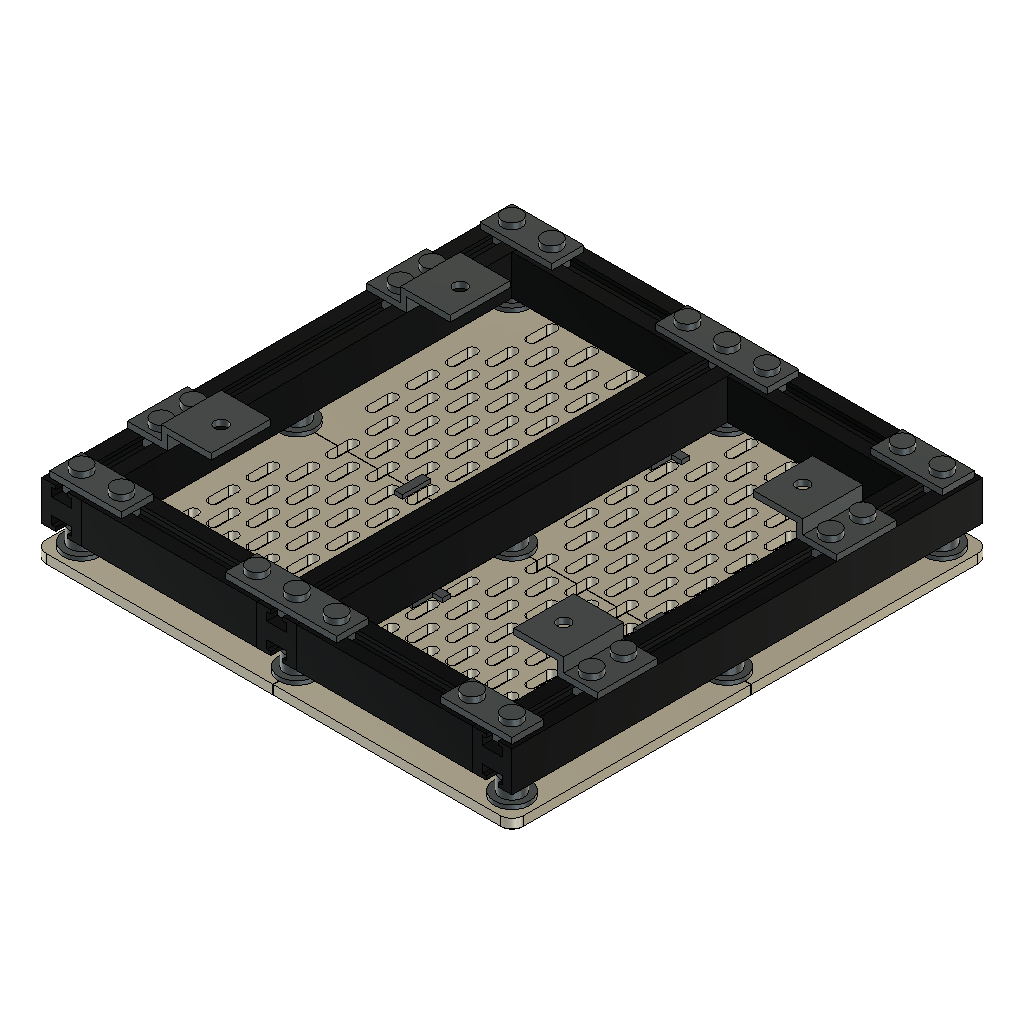
frame-assembly-v02 (Autodesk Fusion 360 design; units mm, degrees)
part number: 2026-10-27-14-19-07-166
part number: 2026-10-27-14-19-07-529
part number: 2026-10-27-14-19-09-809
part number: 2026-10-27-14-19-13-268
part number: 2026-10-27-14-19-18-051
part number: 2026-10-27-14-19-24-139
part number: 2026-10-27-14-19-25-781
part number: 2026-10-27-14-19-27-655
part number: 2026-10-27-14-19-31-529
part number: 2026-10-27-14-19-36-193
part number: 2026-10-27-14-19-39-612
part number: 2026-10-27-14-19-43-334
part number: 2026-10-27-14-19-47-364
part number: 2026-10-27-14-19-51-904
part number: 2026-10-27-14-19-56-573
part number: 2026-10-27-14-20-01-501
part number: 2026-10-27-14-20-06-731
part number: 2026-10-27-14-20-09-539
part number: 2026-10-27-14-20-12-443
part number: 2026-10-27-14-20-16-554
part number: 2026-10-27-14-20-19-669
part number: 2026-10-27-14-20-23-649
part number: 2026-10-27-14-20-26-963
part number: 2026-10-27-14-20-30-408
part number: 2026-10-27-14-20-35-629
part number: 2026-10-27-14-20-39-250
part number: 2026-10-27-14-20-43-608
part number: 2026-10-27-14-20-47-417
part number: 2026-10-27-14-20-51-282
part number: 2026-10-27-14-20-56-790
part number: 2026-10-27-14-21-00-901
part number: 2026-10-27-14-21-05-969
part number: 2026-10-27-14-21-10-301
part number: 2026-10-27-14-21-14-740
part number: 2026-10-27-14-21-20-864
part number: 2026-10-27-14-21-25-515
part number: 2026-10-27-14-21-31-135
part number: 2026-10-27-14-21-36-008
part number: 2026-10-27-14-21-40-945
part number: 2026-10-27-14-21-47-902
part number: 2026-10-27-14-21-53-029
part number: 2026-10-27-14-21-59-262
part number: 2026-10-27-14-22-04-647
part number: 2026-10-27-14-22-10-209
part number: 2026-10-27-14-22-17-939
part number: 2026-10-27-14-22-23-788
part number: 2026-10-27-14-22-30-837
part number: 2026-10-27-14-22-36-914
part number: 2026-10-27-14-22-43-023
part number: 2026-10-27-14-22-51-516
part number: 2026-10-27-14-22-58-163
part number: 2026-10-27-14-23-05-832
part number: 2026-10-27-14-23-12-387
part number: 2026-10-27-14-23-18-901
part number: 2026-10-27-14-23-27-984
part number: 2026-10-27-14-23-34-860
part number: 2026-10-27-14-23-42-988
part number: 2026-10-27-14-23-50-025
part number: 2026-10-27-14-23-57-272
part number: 2026-10-27-14-24-07-126
part number: 2026-10-27-14-24-14-511
part number: 2026-10-27-14-25-58-757
part number: 2026-10-27-14-26-07-708
part number: 2026-10-27-14-26-15-601
part number: 2026-10-27-14-26-28-880
part number: 2026-10-27-14-26-37-122
part number: 2026-10-27-14-26-46-848
part number: 2026-10-27-14-26-56-585
part number: 2026-10-27-14-27-05-195
part number: 2026-10-27-14-27-19-539
part number: 2026-10-27-14-27-28-473
part number: 2026-10-27-14-27-43-465
part number: 2026-10-27-14-27-53-465
part number: 2026-10-27-14-28-04-862
part number: 2026-10-27-14-28-15-884
part number: 2026-10-27-14-28-25-517
part number: 2026-10-27-14-28-41-860
part number: 2026-10-27-14-28-51-770
part number: 2026-10-27-14-29-29-498
part number: 2026-10-27-14-29-41-777
part number: 2026-10-27-14-29-52-480
part number: 2026-10-27-14-30-10-482
part number: 2026-10-27-14-30-21-478
part number: 2026-10-27-14-30-34-709
part number: 2026-10-27-14-30-47-817
part number: 2026-10-27-14-30-59-317
part number: 2026-10-27-14-31-18-533
part number: 2026-10-27-14-31-30-323
part number: 2026-10-27-14-31-49-934
part number: 2026-10-27-14-32-02-066
part number: 2026-10-27-14-32-16-521
part number: 2026-10-27-14-32-30-791
part number: 2026-10-27-14-32-43-473
part number: 2026-10-27-14-33-04-473
part number: 2026-10-27-14-33-17-387
part number: 2026-10-27-14-34-51-038
part number: 2026-10-27-14-35-27-564
part number: 2026-10-27-14-35-40-483
part number: 2026-10-27-14-36-02-021
part number: 2026-10-27-14-36-15-429
part number: 2026-10-27-14-36-31-161
part number: 2026-10-27-14-37-10-809
part number: 2026-10-27-14-37-25-035
part number: 2026-10-27-14-37-48-193
part number: 2026-10-27-14-38-03-120
part number: 2026-10-27-14-38-20-090
part number: 2026-10-27-14-39-02-547
part number: 2026-10-27-14-39-17-368
part number: 2026-10-27-14-39-42-212
part number: 2026-10-27-14-39-58-334
part number: 2026-10-27-14-40-16-332
part number: 2026-10-27-14-41-01-723
part number: 2026-10-27-14-41-17-623
part number: 2026-10-27-14-41-44-437
part number: 2026-10-27-14-42-00-770
Autodesk Fusion 360 part; units mm, degrees
(part 1 of 7)
sketch "01 Panel blank sketch" plane through (0, 0, 0) normal (0, 0, 1) x (1, 0, 0) in component "Panel lower left"
  line L0 (0.1, 0.1) -> (119.9, 0.1)
  line L1 (119.9, 0.1) -> (119.9, 119.9)
  line L2 (119.9, 119.9) -> (0.1, 119.9)
  line L3 (0.1, 119.9) -> (0.1, 0.1)
  dimension "d31" = 0.1
  dimension "d32" = 0.1
  dimension "d33" = 119.8
  dimension "d34" = 119.8
  constraint horizontal L0
  constraint vertical L1
  constraint horizontal L2
  constraint vertical L3
  measures "d31" horizontal distance of origin L0.start
  measures "d32" vertical distance of origin L0.start
  measures "d33" horizontal distance of L0.start L0.end
  measures "d34" vertical distance of L0.end L1.end
extrude "01 Panel blank" add sketch "01 Panel blank sketch" along normal blind 5 makes body 1 in component "Panel lower left"
fillet "02 Rounded exterior corner" radius 6 1 edges at (0.1, 0.1, 2.5) on bodies 1 in component "Panel lower left"
sketch "03 A main constrained seed" plane through (0, 0, 0) normal (0, 0, 1) x (1, 0, 0) in component "Panel lower left"
  line L0 (47.5, 25) -> (47.5, 35)
  arc A0 (47.5, 35) -> (42.5, 35) centre (45, 35) ccw
  line L1 (42.5, 35) -> (42.5, 25)
  arc A1 (42.5, 25) -> (47.5, 25) centre (45, 25) ccw
  line L2 (45, 25) -> (45, 35) construction
  line L3 (45, 25) -> (55, 25) construction
  dimension "d39" = 5
  dimension "d40" = 10
  dimension "d41" = 90
  dimension "d42" = 10
  dimension "d43" = 45
  dimension "d44" = 25
  constraint tangent L0 A0
  constraint tangent A0 L1
  constraint tangent L1 A1
  constraint tangent L0 A1
  constraint parallel L0 L1
  constraint horizontal L3
  measures "d39" diameter of A0
  measures "d40" distance of A1.centre A0.centre
  measures "d41" angle of L2 L3
  measures "d42" horizontal distance of A1.centre L3.end
  measures "d43" horizontal distance of origin A1.centre
  measures "d44" vertical distance of origin A1.centre
extrude "03 A main through cut" cut sketch "03 A main constrained seed" along normal blind 5 bodies 1 in component "Panel lower left"
pattern_linear "03 A main lattice" count 4 spacing 20 along (1, 0, 0) count 5 spacing 20 along (0, 1, 0) of "03 A main through cut" in component "Panel lower left"
sketch "04 A end strip constrained seed" plane through (0, 0, 0) normal (0, 0, 1) x (1, 0, 0) in component "Panel lower left"
  line L0 (27.5, 45) -> (27.5, 55)
  arc A0 (27.5, 55) -> (22.5, 55) centre (25, 55) ccw
  line L1 (22.5, 55) -> (22.5, 45)
  arc A1 (22.5, 45) -> (27.5, 45) centre (25, 45) ccw
  line L2 (25, 45) -> (25, 55) construction
  line L3 (25, 45) -> (35, 45) construction
  dimension "d51" = 5
  dimension "d52" = 10
  dimension "d53" = 90
  dimension "d54" = 10
  dimension "d55" = 25
  dimension "d56" = 45
  constraint tangent L0 A0
  constraint tangent A0 L1
  constraint tangent L1 A1
  constraint tangent L0 A1
  constraint parallel L0 L1
  constraint horizontal L3
  measures "d51" diameter of A0
  measures "d52" distance of A1.centre A0.centre
  measures "d53" angle of L2 L3
  measures "d54" horizontal distance of A1.centre L3.end
  measures "d55" horizontal distance of origin A1.centre
  measures "d56" vertical distance of origin A1.centre
extrude "04 A end strip through cut" cut sketch "04 A end strip constrained seed" along normal blind 5 bodies 1 in component "Panel lower left"
pattern_linear "04 A end strip lattice" count 1 spacing 20 along (1, 0, 0) count 3 spacing 20 along (0, 1, 0) of "04 A end strip through cut" in component "Panel lower left"
sketch "05 B main constrained seed" plane through (0, 0, 0) normal (0, 0, 1) x (1, 0, 0) in component "Panel lower left"
  line L0 (37.5, 15) -> (37.5, 25)
  arc A0 (37.5, 25) -> (32.5, 25) centre (35, 25) ccw
  line L1 (32.5, 25) -> (32.5, 15)
  arc A1 (32.5, 15) -> (37.5, 15) centre (35, 15) ccw
  line L2 (35, 15) -> (35, 25) construction
  line L3 (35, 15) -> (45, 15) construction
  dimension "d63" = 5
  dimension "d64" = 10
  dimension "d65" = 90
  dimension "d66" = 10
  dimension "d67" = 35
  dimension "d68" = 15
  constraint tangent L0 A0
  constraint tangent A0 L1
  constraint tangent L1 A1
  constraint tangent L0 A1
  constraint parallel L0 L1
  constraint horizontal L3
  measures "d63" diameter of A0
  measures "d64" distance of A1.centre A0.centre
  measures "d65" angle of L2 L3
  measures "d66" horizontal distance of A1.centre L3.end
  measures "d67" horizontal distance of origin A1.centre
  measures "d68" vertical distance of origin A1.centre
extrude "05 B main through cut" cut sketch "05 B main constrained seed" along normal blind 5 bodies 1 in component "Panel lower left"
pattern_linear "05 B main lattice" count 4 spacing 20 along (1, 0, 0) count 6 spacing 20 along (0, 1, 0) of "05 B main through cut" in component "Panel lower left"
sketch "06 B end strip constrained seed" plane through (0, 0, 0) normal (0, 0, 1) x (1, 0, 0) in component "Panel lower left"
  line L0 (117.5, 35) -> (117.5, 45)
  arc A0 (117.5, 45) -> (112.5, 45) centre (115, 45) ccw
  line L1 (112.5, 45) -> (112.5, 35)
  arc A1 (112.5, 35) -> (117.5, 35) centre (115, 35) ccw
  line L2 (115, 35) -> (115, 45) construction
  line L3 (115, 35) -> (125, 35) construction
  dimension "d75" = 5
  dimension "d76" = 10
  dimension "d77" = 90
  dimension "d78" = 10
  dimension "d79" = 115
  dimension "d80" = 35
  constraint tangent L0 A0
  constraint tangent A0 L1
  constraint tangent L1 A1
  constraint tangent L0 A1
  constraint parallel L0 L1
  constraint horizontal L3
  measures "d75" diameter of A0
  measures "d76" distance of A1.centre A0.centre
  measures "d77" angle of L2 L3
  measures "d78" horizontal distance of A1.centre L3.end
  measures "d79" horizontal distance of origin A1.centre
  measures "d80" vertical distance of origin A1.centre
extrude "06 B end strip through cut" cut sketch "06 B end strip constrained seed" along normal blind 5 bodies 1 in component "Panel lower left"
pattern_linear "06 B end strip lattice" count 1 spacing 20 along (1, 0, 0) count 4 spacing 20 along (0, 1, 0) of "06 B end strip through cut" in component "Panel lower left"
sketch "07 Shared node clearance sketch" plane through (0, 0, 0) normal (0, 0, 1) x (1, 0, 0) in component "Panel lower left"
  circle A0 centre (12, 12) radius 4.2
  dimension "d87" = 12
  dimension "d88" = 12
  dimension "d89" = 8.4
  measures "d87" horizontal distance of origin A0.centre
  measures "d88" vertical distance of origin A0.centre
  measures "d89" diameter of A0
extrude "07 Shared node clearance" cut sketch "07 Shared node clearance sketch" along normal blind 5 bodies 1 in component "Panel lower left"
sketch "07 Shared node clearance sketch (1)" plane through (0, 0, 0) normal (0, 0, 1) x (1, 0, 0) in component "Panel lower left"
  circle A0 centre (12, 120) radius 4.2
  dimension "d92" = 12
  dimension "d93" = 120
  dimension "d94" = 8.4
  measures "d92" horizontal distance of origin A0.centre
  measures "d93" vertical distance of origin A0.centre
  measures "d94" diameter of A0
extrude "07 Shared node clearance (1)" cut sketch "07 Shared node clearance sketch (1)" along normal blind 5 bodies 1 in component "Panel lower left"
sketch "07 Shared node clearance sketch (2)" plane through (0, 0, 0) normal (0, 0, 1) x (1, 0, 0) in component "Panel lower left"
  circle A0 centre (120, 12) radius 4.2
  dimension "d97" = 120
  dimension "d98" = 12
  dimension "d99" = 8.4
  measures "d97" horizontal distance of origin A0.centre
  measures "d98" vertical distance of origin A0.centre
  measures "d99" diameter of A0
extrude "07 Shared node clearance (2)" cut sketch "07 Shared node clearance sketch (2)" along normal blind 5 bodies 1 in component "Panel lower left"
sketch "07 Shared node clearance sketch (3)" plane through (0, 0, 0) normal (0, 0, 1) x (1, 0, 0) in component "Panel lower left"
  circle A0 centre (120, 120) radius 4.2
  dimension "d102" = 120
  dimension "d103" = 120
  dimension "d104" = 8.4
  measures "d102" horizontal distance of origin A0.centre
  measures "d103" vertical distance of origin A0.centre
  measures "d104" diameter of A0
extrude "07 Shared node clearance (3)" cut sketch "07 Shared node clearance sketch (3)" along normal blind 5 bodies 1 in component "Panel lower left"
fillet "08 Rounded slot entrances and face edges" radius 0.4 2 faces at (7.5667, 63.6667, 0) (7.5667, 63.6667, 0) on bodies 1 in component "Panel lower left"
ref_plane "WorkPlane1" through (0, 0, 5) normal (0, 0, 1) x (1, 0, 0) in component "Panel lower left"
sketch "09 Blind rear key socket sketch" plane through (0, 0, 5) normal (0, 0, 1) x (1, 0, 0) in component "Panel lower left"
  circle A0 centre (115, 70) radius 1.7
  dimension "d111" = 115
  dimension "d112" = 70
  dimension "d113" = 3.4
  measures "d111" horizontal distance of origin A0.centre
  measures "d112" vertical distance of origin A0.centre
  measures "d113" diameter of A0
extrude "09 Blind rear key socket" cut sketch "09 Blind rear key socket sketch" against normal blind 1 bodies 1 in component "Panel lower left"
ref_plane "WorkPlane2" through (0, 0, 5) normal (0, 0, 1) x (1, 0, 0) in component "Panel lower left"
sketch "09 Blind rear key socket sketch (1)" plane through (0, 0, 5) normal (0, 0, 1) x (1, 0, 0) in component "Panel lower left"
  circle A0 centre (70, 115) radius 1.7
  dimension "d118" = 70
  dimension "d119" = 115
  dimension "d120" = 3.4
  measures "d118" horizontal distance of origin A0.centre
  measures "d119" vertical distance of origin A0.centre
  measures "d120" diameter of A0
extrude "09 Blind rear key socket (1)" cut sketch "09 Blind rear key socket sketch (1)" against normal blind 1 bodies 1 in component "Panel lower left"
sketch "01 Panel blank sketch (2)" plane through (0, 0, 0) normal (0, 0, 1) x (1, 0, 0) in component "Panel lower right"
  line L0 (120.1, 0.1) -> (239.9, 0.1)
  line L1 (239.9, 0.1) -> (239.9, 119.9)
  line L2 (239.9, 119.9) -> (120.1, 119.9)
  line L3 (120.1, 119.9) -> (120.1, 0.1)
  dimension "d127" = 120.1
  dimension "d128" = 0.1
  dimension "d129" = 119.8
  dimension "d130" = 119.8
  constraint horizontal L0
  constraint vertical L1
  constraint horizontal L2
  constraint vertical L3
  measures "d127" horizontal distance of origin L0.start
  measures "d128" vertical distance of origin L0.start
  measures "d129" horizontal distance of L0.start L0.end
  measures "d130" vertical distance of L0.end L1.end
extrude "01 Panel blank'" add sketch "01 Panel blank sketch (2)" along normal blind 5 separate body makes body 2 in component "Panel lower right"
fillet "02 Rounded exterior corner'" radius 6 1 edges at (239.9, 0.1, 2.5) on bodies 2 in component "Panel lower right"
sketch "03 A main constrained seed (2)" plane through (0, 0, 0) normal (0, 0, 1) x (1, 0, 0) in component "Panel lower right"
  line L0 (147.5, 25) -> (147.5, 35)
  arc A0 (147.5, 35) -> (142.5, 35) centre (145, 35) ccw
  line L1 (142.5, 35) -> (142.5, 25)
  arc A1 (142.5, 25) -> (147.5, 25) centre (145, 25) ccw
  line L2 (145, 25) -> (145, 35) construction
  line L3 (145, 25) -> (155, 25) construction
  dimension "d135" = 5
  dimension "d136" = 10
  dimension "d137" = 90
  dimension "d138" = 10
  dimension "d139" = 145
  dimension "d140" = 25
  constraint tangent L0 A0
  constraint tangent A0 L1
  constraint tangent L1 A1
  constraint tangent L0 A1
  constraint parallel L0 L1
  constraint horizontal L3
  measures "d135" diameter of A0
  measures "d136" distance of A1.centre A0.centre
  measures "d137" angle of L2 L3
  measures "d138" horizontal distance of A1.centre L3.end
  measures "d139" horizontal distance of origin A1.centre
  measures "d140" vertical distance of origin A1.centre
extrude "03 A main through cut'" cut sketch "03 A main constrained seed (2)" along normal blind 5 bodies 2 in component "Panel lower right"
pattern_linear "03 A main lattice'" count 4 spacing 20 along (1, 0, 0) count 5 spacing 20 along (0, 1, 0) of "03 A main through cut'" in component "Panel lower right"
sketch "04 A end strip constrained seed (2)" plane through (0, 0, 0) normal (0, 0, 1) x (1, 0, 0) in component "Panel lower right"
  line L0 (127.5, 45) -> (127.5, 55)
  arc A0 (127.5, 55) -> (122.5, 55) centre (125, 55) ccw
  line L1 (122.5, 55) -> (122.5, 45)
  arc A1 (122.5, 45) -> (127.5, 45) centre (125, 45) ccw
  line L2 (125, 45) -> (125, 55) construction
  line L3 (125, 45) -> (135, 45) construction
  dimension "d147" = 5
  dimension "d148" = 10
  dimension "d149" = 90
  dimension "d150" = 10
  dimension "d151" = 125
  dimension "d152" = 45
  constraint tangent L0 A0
  constraint tangent A0 L1
  constraint tangent L1 A1
  constraint tangent L0 A1
  constraint parallel L0 L1
  constraint horizontal L3
  measures "d147" diameter of A0
  measures "d148" distance of A1.centre A0.centre
  measures "d149" angle of L2 L3
  measures "d150" horizontal distance of A1.centre L3.end
  measures "d151" horizontal distance of origin A1.centre
  measures "d152" vertical distance of origin A1.centre
extrude "04 A end strip through cut'" cut sketch "04 A end strip constrained seed (2)" along normal blind 5 bodies 2 in component "Panel lower right"
pattern_linear "04 A end strip lattice'" count 1 spacing 20 along (1, 0, 0) count 3 spacing 20 along (0, 1, 0) of "04 A end strip through cut'" in component "Panel lower right"
sketch "05 B main constrained seed (2)" plane through (0, 0, 0) normal (0, 0, 1) x (1, 0, 0) in component "Panel lower right"
  line L0 (137.5, 15) -> (137.5, 25)
  arc A0 (137.5, 25) -> (132.5, 25) centre (135, 25) ccw
  line L1 (132.5, 25) -> (132.5, 15)
  arc A1 (132.5, 15) -> (137.5, 15) centre (135, 15) ccw
  line L2 (135, 15) -> (135, 25) construction
  line L3 (135, 15) -> (145, 15) construction
  dimension "d159" = 5
  dimension "d160" = 10
  dimension "d161" = 90
  dimension "d162" = 10
  dimension "d163" = 135
  dimension "d164" = 15
  constraint tangent L0 A0
  constraint tangent A0 L1
  constraint tangent L1 A1
  constraint tangent L0 A1
  constraint parallel L0 L1
  constraint horizontal L3
  measures "d159" diameter of A0
  measures "d160" distance of A1.centre A0.centre
  measures "d161" angle of L2 L3
  measures "d162" horizontal distance of A1.centre L3.end
  measures "d163" horizontal distance of origin A1.centre
  measures "d164" vertical distance of origin A1.centre
extrude "05 B main through cut'" cut sketch "05 B main constrained seed (2)" along normal blind 5 bodies 2 in component "Panel lower right"
pattern_linear "05 B main lattice'" count 4 spacing 20 along (1, 0, 0) count 6 spacing 20 along (0, 1, 0) of "05 B main through cut'" in component "Panel lower right"
sketch "06 B end strip constrained seed (2)" plane through (0, 0, 0) normal (0, 0, 1) x (1, 0, 0) in component "Panel lower right"
  line L0 (217.5, 35) -> (217.5, 45)
  arc A0 (217.5, 45) -> (212.5, 45) centre (215, 45) ccw
  line L1 (212.5, 45) -> (212.5, 35)
  arc A1 (212.5, 35) -> (217.5, 35) centre (215, 35) ccw
  line L2 (215, 35) -> (215, 45) construction
  line L3 (215, 35) -> (225, 35) construction
  dimension "d171" = 5
  dimension "d172" = 10
  dimension "d173" = 90
  dimension "d174" = 10
  dimension "d175" = 215
  dimension "d176" = 35
  constraint tangent L0 A0
  constraint tangent A0 L1
  constraint tangent L1 A1
  constraint tangent L0 A1
  constraint parallel L0 L1
  constraint horizontal L3
  measures "d171" diameter of A0
  measures "d172" distance of A1.centre A0.centre
  measures "d173" angle of L2 L3
  measures "d174" horizontal distance of A1.centre L3.end
  measures "d175" horizontal distance of origin A1.centre
  measures "d176" vertical distance of origin A1.centre
extrude "06 B end strip through cut'" cut sketch "06 B end strip constrained seed (2)" along normal blind 5 bodies 2 in component "Panel lower right"
pattern_linear "06 B end strip lattice'" count 1 spacing 20 along (1, 0, 0) count 4 spacing 20 along (0, 1, 0) of "06 B end strip through cut'" in component "Panel lower right"
sketch "07 Shared node clearance sketch (4)" plane through (0, 0, 0) normal (0, 0, 1) x (1, 0, 0) in component "Panel lower right"
  circle A0 centre (120, 12) radius 4.2
  dimension "d183" = 120
  dimension "d184" = 12
  dimension "d185" = 8.4
  measures "d183" horizontal distance of origin A0.centre
  measures "d184" vertical distance of origin A0.centre
  measures "d185" diameter of A0
extrude "07 Shared node clearance'" cut sketch "07 Shared node clearance sketch (4)" along normal blind 5 bodies 2 in component "Panel lower right"
sketch "07 Shared node clearance sketch (1) (2)" plane through (0, 0, 0) normal (0, 0, 1) x (1, 0, 0) in component "Panel lower right"
  circle A0 centre (120, 120) radius 4.2
  dimension "d188" = 120
  dimension "d189" = 120
  dimension "d190" = 8.4
  measures "d188" horizontal distance of origin A0.centre
  measures "d189" vertical distance of origin A0.centre
  measures "d190" diameter of A0
extrude "07 Shared node clearance (1)'" cut sketch "07 Shared node clearance sketch (1) (2)" along normal blind 5 bodies 2 in component "Panel lower right"
sketch "07 Shared node clearance sketch (2) (2)" plane through (0, 0, 0) normal (0, 0, 1) x (1, 0, 0) in component "Panel lower right"
  circle A0 centre (228, 12) radius 4.2
  dimension "d193" = 228
  dimension "d194" = 12
  dimension "d195" = 8.4
  measures "d193" horizontal distance of origin A0.centre
  measures "d194" vertical distance of origin A0.centre
  measures "d195" diameter of A0
extrude "07 Shared node clearance (2)'" cut sketch "07 Shared node clearance sketch (2) (2)" along normal blind 5 bodies 2 in component "Panel lower right"
sketch "07 Shared node clearance sketch (3) (2)" plane through (0, 0, 0) normal (0, 0, 1) x (1, 0, 0) in component "Panel lower right"
  circle A0 centre (228, 120) radius 4.2
  dimension "d198" = 228
  dimension "d199" = 120
  dimension "d200" = 8.4
  measures "d198" horizontal distance of origin A0.centre
  measures "d199" vertical distance of origin A0.centre
  measures "d200" diameter of A0
extrude "07 Shared node clearance (3)'" cut sketch "07 Shared node clearance sketch (3) (2)" along normal blind 5 bodies 2 in component "Panel lower right"
fillet "08 Rounded slot entrances and face edges'" radius 0.4 2 faces at (232.4333, 63.6667, 0) (232.4333, 63.6667, 0) on bodies 2 in component "Panel lower right"
ref_plane "WorkPlane1" through (0, 0, 5) normal (0, 0, 1) x (1, 0, 0) in component "Panel lower right"
sketch "09 Blind rear key socket sketch (2)" plane through (0, 0, 5) normal (0, 0, 1) x (1, 0, 0) in component "Panel lower right"
  circle A0 centre (125, 80) radius 1.7
  dimension "d207" = 125
  dimension "d208" = 80
  dimension "d209" = 3.4
  measures "d207" horizontal distance of origin A0.centre
  measures "d208" vertical distance of origin A0.centre
  measures "d209" diameter of A0
extrude "09 Blind rear key socket'" cut sketch "09 Blind rear key socket sketch (2)" against normal blind 1 bodies 2 in component "Panel lower right"
ref_plane "WorkPlane2" through (0, 0, 5) normal (0, 0, 1) x (1, 0, 0) in component "Panel lower right"
sketch "09 Blind rear key socket sketch (1) (2)" plane through (0, 0, 5) normal (0, 0, 1) x (1, 0, 0) in component "Panel lower right"
  circle A0 centre (190, 115) radius 1.7
  dimension "d214" = 190
  dimension "d215" = 115
  dimension "d216" = 3.4
  measures "d214" horizontal distance of origin A0.centre
  measures "d215" vertical distance of origin A0.centre
  measures "d216" diameter of A0
extrude "09 Blind rear key socket (1)'" cut sketch "09 Blind rear key socket sketch (1) (2)" against normal blind 1 bodies 2 in component "Panel lower right"
sketch "01 Panel blank sketch (3)" plane through (0, 0, 0) normal (0, 0, 1) x (1, 0, 0) in component "Panel upper left"
  line L0 (0.1, 120.1) -> (119.9, 120.1)
  line L1 (119.9, 120.1) -> (119.9, 239.9)
  line L2 (119.9, 239.9) -> (0.1, 239.9)
  line L3 (0.1, 239.9) -> (0.1, 120.1)
  dimension "d223" = 0.1
  dimension "d224" = 120.1
  dimension "d225" = 119.8
  dimension "d226" = 119.8
  constraint horizontal L0
  constraint vertical L1
  constraint horizontal L2
  constraint vertical L3
  measures "d223" horizontal distance of origin L0.start
  measures "d224" vertical distance of origin L0.start
  measures "d225" horizontal distance of L0.start L0.end
  measures "d226" vertical distance of L0.end L1.end
extrude "01 Panel blank''" add sketch "01 Panel blank sketch (3)" along normal blind 5 separate body makes body 3 in component "Panel upper left"
fillet "02 Rounded exterior corner''" radius 6 1 edges at (0.1, 239.9, 2.5) on bodies 3 in component "Panel upper left"
sketch "03 A main constrained seed (3)" plane through (0, 0, 0) normal (0, 0, 1) x (1, 0, 0) in component "Panel upper left"
  line L0 (47.5, 125) -> (47.5, 135)
  arc A0 (47.5, 135) -> (42.5, 135) centre (45, 135) ccw
  line L1 (42.5, 135) -> (42.5, 125)
  arc A1 (42.5, 125) -> (47.5, 125) centre (45, 125) ccw
  line L2 (45, 125) -> (45, 135) construction
  line L3 (45, 125) -> (55, 125) construction
  dimension "d231" = 5
  dimension "d232" = 10
  dimension "d233" = 90
  dimension "d234" = 10
  dimension "d235" = 45
  dimension "d236" = 125
  constraint tangent L0 A0
  constraint tangent A0 L1
  constraint tangent L1 A1
  constraint tangent L0 A1
  constraint parallel L0 L1
  constraint horizontal L3
  measures "d231" diameter of A0
  measures "d232" distance of A1.centre A0.centre
  measures "d233" angle of L2 L3
  measures "d234" horizontal distance of A1.centre L3.end
  measures "d235" horizontal distance of origin A1.centre
  measures "d236" vertical distance of origin A1.centre
extrude "03 A main through cut''" cut sketch "03 A main constrained seed (3)" along normal blind 5 bodies 3 in component "Panel upper left"
pattern_linear "03 A main lattice''" count 4 spacing 20 along (1, 0, 0) count 5 spacing 20 along (0, 1, 0) of "03 A main through cut''" in component "Panel upper left"
sketch "04 A end strip constrained seed (3)" plane through (0, 0, 0) normal (0, 0, 1) x (1, 0, 0) in component "Panel upper left"
  line L0 (27.5, 145) -> (27.5, 155)
  arc A0 (27.5, 155) -> (22.5, 155) centre (25, 155) ccw
  line L1 (22.5, 155) -> (22.5, 145)
  arc A1 (22.5, 145) -> (27.5, 145) centre (25, 145) ccw
  line L2 (25, 145) -> (25, 155) construction
  line L3 (25, 145) -> (35, 145) construction
  dimension "d243" = 5
  dimension "d244" = 10
  dimension "d245" = 90
  dimension "d246" = 10
  dimension "d247" = 25
  dimension "d248" = 145
  constraint tangent L0 A0
  constraint tangent A0 L1
  constraint tangent L1 A1
  constraint tangent L0 A1
  constraint parallel L0 L1
  constraint horizontal L3
  measures "d243" diameter of A0
  measures "d244" distance of A1.centre A0.centre
  measures "d245" angle of L2 L3
  measures "d246" horizontal distance of A1.centre L3.end
  measures "d247" horizontal distance of origin A1.centre
  measures "d248" vertical distance of origin A1.centre
extrude "04 A end strip through cut''" cut sketch "04 A end strip constrained seed (3)" along normal blind 5 bodies 3 in component "Panel upper left"
pattern_linear "04 A end strip lattice''" count 1 spacing 20 along (1, 0, 0) count 3 spacing 20 along (0, 1, 0) of "04 A end strip through cut''" in component "Panel upper left"
sketch "05 B main constrained seed (3)" plane through (0, 0, 0) normal (0, 0, 1) x (1, 0, 0) in component "Panel upper left"
  line L0 (37.5, 115) -> (37.5, 125)
  arc A0 (37.5, 125) -> (32.5, 125) centre (35, 125) ccw
  line L1 (32.5, 125) -> (32.5, 115)
  arc A1 (32.5, 115) -> (37.5, 115) centre (35, 115) ccw
  line L2 (35, 115) -> (35, 125) construction
  line L3 (35, 115) -> (45, 115) construction
  dimension "d255" = 5
  dimension "d256" = 10
  dimension "d257" = 90
  dimension "d258" = 10
  dimension "d259" = 35
  dimension "d260" = 115
  constraint tangent L0 A0
  constraint tangent A0 L1
  constraint tangent L1 A1
  constraint tangent L0 A1
  constraint parallel L0 L1
  constraint horizontal L3
  measures "d255" diameter of A0
  measures "d256" distance of A1.centre A0.centre
  measures "d257" angle of L2 L3
  measures "d258" horizontal distance of A1.centre L3.end
  measures "d259" horizontal distance of origin A1.centre
  measures "d260" vertical distance of origin A1.centre
extrude "05 B main through cut''" cut sketch "05 B main constrained seed (3)" along normal blind 5 bodies 3 in component "Panel upper left"
pattern_linear "05 B main lattice''" count 4 spacing 20 along (1, 0, 0) count 6 spacing 20 along (0, 1, 0) of "05 B main through cut''" in component "Panel upper left"
sketch "06 B end strip constrained seed (3)" plane through (0, 0, 0) normal (0, 0, 1) x (1, 0, 0) in component "Panel upper left"
  line L0 (117.5, 135) -> (117.5, 145)
  arc A0 (117.5, 145) -> (112.5, 145) centre (115, 145) ccw
  line L1 (112.5, 145) -> (112.5, 135)
  arc A1 (112.5, 135) -> (117.5, 135) centre (115, 135) ccw
  line L2 (115, 135) -> (115, 145) construction
  line L3 (115, 135) -> (125, 135) construction
  dimension "d267" = 5
  dimension "d268" = 10
  dimension "d269" = 90
  dimension "d270" = 10
  dimension "d271" = 115
  dimension "d272" = 135
  constraint tangent L0 A0
  constraint tangent A0 L1
  constraint tangent L1 A1
  constraint tangent L0 A1
  constraint parallel L0 L1
  constraint horizontal L3
  measures "d267" diameter of A0
  measures "d268" distance of A1.centre A0.centre
  measures "d269" angle of L2 L3
  measures "d270" horizontal distance of A1.centre L3.end
  measures "d271" horizontal distance of origin A1.centre
  measures "d272" vertical distance of origin A1.centre
extrude "06 B end strip through cut''" cut sketch "06 B end strip constrained seed (3)" along normal blind 5 bodies 3 in component "Panel upper left"
pattern_linear "06 B end strip lattice''" count 1 spacing 20 along (1, 0, 0) count 4 spacing 20 along (0, 1, 0) of "06 B end strip through cut''" in component "Panel upper left"
sketch "07 Shared node clearance sketch (5)" plane through (0, 0, 0) normal (0, 0, 1) x (1, 0, 0) in component "Panel upper left"
  circle A0 centre (12, 120) radius 4.2
  dimension "d279" = 12
  dimension "d280" = 120
  dimension "d281" = 8.4
  measures "d279" horizontal distance of origin A0.centre
  measures "d280" vertical distance of origin A0.centre
  measures "d281" diameter of A0
extrude "07 Shared node clearance''" cut sketch "07 Shared node clearance sketch (5)" along normal blind 5 bodies 3 in component "Panel upper left"
sketch "07 Shared node clearance sketch (1) (3)" plane through (0, 0, 0) normal (0, 0, 1) x (1, 0, 0) in component "Panel upper left"
  circle A0 centre (12, 228) radius 4.2
  dimension "d284" = 12
  dimension "d285" = 228
  dimension "d286" = 8.4
  measures "d284" horizontal distance of origin A0.centre
  measures "d285" vertical distance of origin A0.centre
  measures "d286" diameter of A0
extrude "07 Shared node clearance (1)''" cut sketch "07 Shared node clearance sketch (1) (3)" along normal blind 5 bodies 3 in component "Panel upper left"
sketch "07 Shared node clearance sketch (2) (3)" plane through (0, 0, 0) normal (0, 0, 1) x (1, 0, 0) in component "Panel upper left"
  circle A0 centre (120, 120) radius 4.2
  dimension "d289" = 120
  dimension "d290" = 120
  dimension "d291" = 8.4
  measures "d289" horizontal distance of origin A0.centre
  measures "d290" vertical distance of origin A0.centre
  measures "d291" diameter of A0
extrude "07 Shared node clearance (2)''" cut sketch "07 Shared node clearance sketch (2) (3)" along normal blind 5 bodies 3 in component "Panel upper left"
sketch "07 Shared node clearance sketch (3) (3)" plane through (0, 0, 0) normal (0, 0, 1) x (1, 0, 0) in component "Panel upper left"
  circle A0 centre (120, 228) radius 4.2
  dimension "d294" = 120
  dimension "d295" = 228
  dimension "d296" = 8.4
  measures "d294" horizontal distance of origin A0.centre
  measures "d295" vertical distance of origin A0.centre
  measures "d296" diameter of A0
extrude "07 Shared node clearance (3)''" cut sketch "07 Shared node clearance sketch (3) (3)" along normal blind 5 bodies 3 in component "Panel upper left"
fillet "08 Rounded slot entrances and face edges''" radius 0.4 2 faces at (7.5667, 176.3333, 0) (7.5667, 176.3333, 0) on bodies 3 in component "Panel upper left"
ref_plane "WorkPlane1" through (0, 0, 5) normal (0, 0, 1) x (1, 0, 0) in component "Panel upper left"
sketch "09 Blind rear key socket sketch (3)" plane through (0, 0, 5) normal (0, 0, 1) x (1, 0, 0) in component "Panel upper left"
  circle A0 centre (115, 190) radius 1.7
  dimension "d303" = 115
  dimension "d304" = 190
  dimension "d305" = 3.4
  measures "d303" horizontal distance of origin A0.centre
  measures "d304" vertical distance of origin A0.centre
  measures "d305" diameter of A0
extrude "09 Blind rear key socket''" cut sketch "09 Blind rear key socket sketch (3)" against normal blind 1 bodies 3 in component "Panel upper left"
ref_plane "WorkPlane2" through (0, 0, 5) normal (0, 0, 1) x (1, 0, 0) in component "Panel upper left"
sketch "09 Blind rear key socket sketch (1) (3)" plane through (0, 0, 5) normal (0, 0, 1) x (1, 0, 0) in component "Panel upper left"
  circle A0 centre (70, 125) radius 1.7
  dimension "d310" = 70
  dimension "d311" = 125
  dimension "d312" = 3.4
  measures "d310" horizontal distance of origin A0.centre
  measures "d311" vertical distance of origin A0.centre
  measures "d312" diameter of A0
extrude "09 Blind rear key socket (1)''" cut sketch "09 Blind rear key socket sketch (1) (3)" against normal blind 1 bodies 3 in component "Panel upper left"
sketch "01 Panel blank sketch (4)" plane through (0, 0, 0) normal (0, 0, 1) x (1, 0, 0) in component "Panel upper right"
  line L0 (120.1, 120.1) -> (239.9, 120.1)
  line L1 (239.9, 120.1) -> (239.9, 239.9)
  line L2 (239.9, 239.9) -> (120.1, 239.9)
  line L3 (120.1, 239.9) -> (120.1, 120.1)
  dimension "d319" = 120.1
  dimension "d320" = 120.1
  dimension "d321" = 119.8
  dimension "d322" = 119.8
  constraint horizontal L0
  constraint vertical L1
  constraint horizontal L2
  constraint vertical L3
  measures "d319" horizontal distance of origin L0.start
  measures "d320" vertical distance of origin L0.start
  measures "d321" horizontal distance of L0.start L0.end
  measures "d322" vertical distance of L0.end L1.end
extrude "01 Panel blank'''" add sketch "01 Panel blank sketch (4)" along normal blind 5 separate body makes body 4 in component "Panel upper right"
fillet "02 Rounded exterior corner'''" radius 6 1 edges at (239.9, 239.9, 2.5) on bodies 4 in component "Panel upper right"
sketch "03 A main constrained seed (4)" plane through (0, 0, 0) normal (0, 0, 1) x (1, 0, 0) in component "Panel upper right"
  line L0 (147.5, 125) -> (147.5, 135)
  arc A0 (147.5, 135) -> (142.5, 135) centre (145, 135) ccw
  line L1 (142.5, 135) -> (142.5, 125)
  arc A1 (142.5, 125) -> (147.5, 125) centre (145, 125) ccw
  line L2 (145, 125) -> (145, 135) construction
  line L3 (145, 125) -> (155, 125) construction
  dimension "d327" = 5
  dimension "d328" = 10
  dimension "d329" = 90
  dimension "d330" = 10
  dimension "d331" = 145
  dimension "d332" = 125
  constraint tangent L0 A0
  constraint tangent A0 L1
  constraint tangent L1 A1
  constraint tangent L0 A1
  constraint parallel L0 L1
  constraint horizontal L3
  measures "d327" diameter of A0
  measures "d328" distance of A1.centre A0.centre
  measures "d329" angle of L2 L3
  measures "d330" horizontal distance of A1.centre L3.end
  measures "d331" horizontal distance of origin A1.centre
  measures "d332" vertical distance of origin A1.centre
extrude "03 A main through cut'''" cut sketch "03 A main constrained seed (4)" along normal blind 5 bodies 4 in component "Panel upper right"
pattern_linear "03 A main lattice'''" count 4 spacing 20 along (1, 0, 0) count 5 spacing 20 along (0, 1, 0) of "03 A main through cut'''" in component "Panel upper right"
sketch "04 A end strip constrained seed (4)" plane through (0, 0, 0) normal (0, 0, 1) x (1, 0, 0) in component "Panel upper right"
  line L0 (127.5, 145) -> (127.5, 155)
  arc A0 (127.5, 155) -> (122.5, 155) centre (125, 155) ccw
  line L1 (122.5, 155) -> (122.5, 145)
  arc A1 (122.5, 145) -> (127.5, 145) centre (125, 145) ccw
  line L2 (125, 145) -> (125, 155) construction
  line L3 (125, 145) -> (135, 145) construction
  dimension "d339" = 5
  dimension "d340" = 10
  dimension "d341" = 90
  dimension "d342" = 10
  dimension "d343" = 125
  dimension "d344" = 145
  constraint tangent L0 A0
  constraint tangent A0 L1
  constraint tangent L1 A1
  constraint tangent L0 A1
  constraint parallel L0 L1
  constraint horizontal L3
  measures "d339" diameter of A0
  measures "d340" distance of A1.centre A0.centre
  measures "d341" angle of L2 L3
  measures "d342" horizontal distance of A1.centre L3.end
  measures "d343" horizontal distance of origin A1.centre
  measures "d344" vertical distance of origin A1.centre
extrude "04 A end strip through cut'''" cut sketch "04 A end strip constrained seed (4)" along normal blind 5 bodies 4 in component "Panel upper right"
pattern_linear "04 A end strip lattice'''" count 1 spacing 20 along (1, 0, 0) count 3 spacing 20 along (0, 1, 0) of "04 A end strip through cut'''" in component "Panel upper right"
sketch "05 B main constrained seed (4)" plane through (0, 0, 0) normal (0, 0, 1) x (1, 0, 0) in component "Panel upper right"
  line L0 (137.5, 115) -> (137.5, 125)
  arc A0 (137.5, 125) -> (132.5, 125) centre (135, 125) ccw
  line L1 (132.5, 125) -> (132.5, 115)
  arc A1 (132.5, 115) -> (137.5, 115) centre (135, 115) ccw
  line L2 (135, 115) -> (135, 125) construction
  line L3 (135, 115) -> (145, 115) construction
  dimension "d351" = 5
  dimension "d352" = 10
  dimension "d353" = 90
  dimension "d354" = 10
  dimension "d355" = 135
  dimension "d356" = 115
  constraint tangent L0 A0
  constraint tangent A0 L1
  constraint tangent L1 A1
  constraint tangent L0 A1
  constraint parallel L0 L1
  constraint horizontal L3
  measures "d351" diameter of A0
  measures "d352" distance of A1.centre A0.centre
  measures "d353" angle of L2 L3
  measures "d354" horizontal distance of A1.centre L3.end
  measures "d355" horizontal distance of origin A1.centre
  measures "d356" vertical distance of origin A1.centre
extrude "05 B main through cut'''" cut sketch "05 B main constrained seed (4)" along normal blind 5 bodies 4 in component "Panel upper right"
pattern_linear "05 B main lattice'''" count 4 spacing 20 along (1, 0, 0) count 6 spacing 20 along (0, 1, 0) of "05 B main through cut'''" in component "Panel upper right"
sketch "06 B end strip constrained seed (4)" plane through (0, 0, 0) normal (0, 0, 1) x (1, 0, 0) in component "Panel upper right"
  line L0 (217.5, 135) -> (217.5, 145)
  arc A0 (217.5, 145) -> (212.5, 145) centre (215, 145) ccw
  line L1 (212.5, 145) -> (212.5, 135)
  arc A1 (212.5, 135) -> (217.5, 135) centre (215, 135) ccw
  line L2 (215, 135) -> (215, 145) construction
  line L3 (215, 135) -> (225, 135) construction
  dimension "d363" = 5
  dimension "d364" = 10
  dimension "d365" = 90
  dimension "d366" = 10
  dimension "d367" = 215
  dimension "d368" = 135
  constraint tangent L0 A0
  constraint tangent A0 L1
  constraint tangent L1 A1
  constraint tangent L0 A1
  constraint parallel L0 L1
  constraint horizontal L3
  measures "d363" diameter of A0
  measures "d364" distance of A1.centre A0.centre
  measures "d365" angle of L2 L3
  measures "d366" horizontal distance of A1.centre L3.end
  measures "d367" horizontal distance of origin A1.centre
  measures "d368" vertical distance of origin A1.centre
extrude "06 B end strip through cut'''" cut sketch "06 B end strip constrained seed (4)" along normal blind 5 bodies 4 in component "Panel upper right"
pattern_linear "06 B end strip lattice'''" count 1 spacing 20 along (1, 0, 0) count 4 spacing 20 along (0, 1, 0) of "06 B end strip through cut'''" in component "Panel upper right"
sketch "07 Shared node clearance sketch (6)" plane through (0, 0, 0) normal (0, 0, 1) x (1, 0, 0) in component "Panel upper right"
  circle A0 centre (120, 120) radius 4.2
  dimension "d375" = 120
  dimension "d376" = 120
  dimension "d377" = 8.4
  measures "d375" horizontal distance of origin A0.centre
  measures "d376" vertical distance of origin A0.centre
  measures "d377" diameter of A0
extrude "07 Shared node clearance'''" cut sketch "07 Shared node clearance sketch (6)" along normal blind 5 bodies 4 in component "Panel upper right"
sketch "07 Shared node clearance sketch (1) (4)" plane through (0, 0, 0) normal (0, 0, 1) x (1, 0, 0) in component "Panel upper right"
  circle A0 centre (120, 228) radius 4.2
  dimension "d380" = 120
  dimension "d381" = 228
  dimension "d382" = 8.4
  measures "d380" horizontal distance of origin A0.centre
  measures "d381" vertical distance of origin A0.centre
  measures "d382" diameter of A0
extrude "07 Shared node clearance (1)'''" cut sketch "07 Shared node clearance sketch (1) (4)" along normal blind 5 bodies 4 in component "Panel upper right"
sketch "07 Shared node clearance sketch (2) (4)" plane through (0, 0, 0) normal (0, 0, 1) x (1, 0, 0) in component "Panel upper right"
  circle A0 centre (228, 120) radius 4.2
  dimension "d385" = 228
  dimension "d386" = 120
  dimension "d387" = 8.4
  measures "d385" horizontal distance of origin A0.centre
  measures "d386" vertical distance of origin A0.centre
  measures "d387" diameter of A0
extrude "07 Shared node clearance (2)'''" cut sketch "07 Shared node clearance sketch (2) (4)" along normal blind 5 bodies 4 in component "Panel upper right"
sketch "07 Shared node clearance sketch (3) (4)" plane through (0, 0, 0) normal (0, 0, 1) x (1, 0, 0) in component "Panel upper right"
  circle A0 centre (228, 228) radius 4.2
  dimension "d390" = 228
  dimension "d391" = 228
  dimension "d392" = 8.4
  measures "d390" horizontal distance of origin A0.centre
  measures "d391" vertical distance of origin A0.centre
  measures "d392" diameter of A0
extrude "07 Shared node clearance (3)'''" cut sketch "07 Shared node clearance sketch (3) (4)" along normal blind 5 bodies 4 in component "Panel upper right"
fillet "08 Rounded slot entrances and face edges'''" radius 0.4 2 faces at (232.4333, 176.3333, 0) (232.4333, 176.3333, 0) on bodies 4 in component "Panel upper right"
ref_plane "WorkPlane1" through (0, 0, 5) normal (0, 0, 1) x (1, 0, 0) in component "Panel upper right"
sketch "09 Blind rear key socket sketch (4)" plane through (0, 0, 5) normal (0, 0, 1) x (1, 0, 0) in component "Panel upper right"
  circle A0 centre (125, 200) radius 1.7
  dimension "d399" = 125
  dimension "d400" = 200
  dimension "d401" = 3.4
  measures "d399" horizontal distance of origin A0.centre
  measures "d400" vertical distance of origin A0.centre
  measures "d401" diameter of A0
extrude "09 Blind rear key socket'''" cut sketch "09 Blind rear key socket sketch (4)" against normal blind 1 bodies 4 in component "Panel upper right"
ref_plane "WorkPlane2" through (0, 0, 5) normal (0, 0, 1) x (1, 0, 0) in component "Panel upper right"
sketch "09 Blind rear key socket sketch (1) (4)" plane through (0, 0, 5) normal (0, 0, 1) x (1, 0, 0) in component "Panel upper right"
  circle A0 centre (190, 125) radius 1.7
  dimension "d406" = 190
  dimension "d407" = 125
  dimension "d408" = 3.4
  measures "d406" horizontal distance of origin A0.centre
  measures "d407" vertical distance of origin A0.centre
  measures "d408" diameter of A0
extrude "09 Blind rear key socket (1)'''" cut sketch "09 Blind rear key socket sketch (1) (4)" against normal blind 1 bodies 4 in component "Panel upper right"
ref_plane "WorkPlane1" through (0, 0, 5) normal (0, 0, 1) x (1, 0, 0) in component "PRINT horizontal alignment key L"
sketch "Key body sketch" plane through (0, 0, 5) normal (0, 0, 1) x (1, 0, 0) in component "PRINT horizontal alignment key L"
  line L0 (68, 113) -> (72, 113)
  line L1 (72, 113) -> (72, 127)
  line L2 (72, 127) -> (68, 127)
  line L3 (68, 127) -> (68, 113)
  dimension "d413" = 68
  dimension "d414" = 113
  dimension "d415" = 4
  dimension "d416" = 14
  constraint horizontal L0
  constraint vertical L1
  constraint horizontal L2
  constraint vertical L3
  measures "d413" horizontal distance of origin L0.start
  measures "d414" vertical distance of origin L0.start
  measures "d415" horizontal distance of L0.start L0.end
  measures "d416" vertical distance of L0.end L1.end
extrude "Key body" add sketch "Key body sketch" along normal blind 2 separate body makes body 5 in component "PRINT horizontal alignment key L"
ref_plane "WorkPlane2" through (0, 0, 5) normal (0, 0, 1) x (1, 0, 0) in component "PRINT horizontal alignment key L"
sketch "Locating peg sketch" plane through (0, 0, 5) normal (0, 0, 1) x (1, 0, 0) in component "PRINT horizontal alignment key L"
  circle A0 centre (70, 115) radius 1.5
  dimension "d421" = 70
  dimension "d422" = 115
  dimension "d423" = 3
  measures "d421" horizontal distance of origin A0.centre
  measures "d422" vertical distance of origin A0.centre
  measures "d423" diameter of A0
extrude "Locating peg" add sketch "Locating peg sketch" against normal blind 0.8 bodies 5 in component "PRINT horizontal alignment key L"
ref_plane "WorkPlane3" through (0, 0, 5) normal (0, 0, 1) x (1, 0, 0) in component "PRINT horizontal alignment key L"
sketch "Locating peg sketch (1)" plane through (0, 0, 5) normal (0, 0, 1) x (1, 0, 0) in component "PRINT horizontal alignment key L"
  circle A0 centre (70, 125) radius 1.5
  dimension "d428" = 70
  dimension "d429" = 125
  dimension "d430" = 3
  measures "d428" horizontal distance of origin A0.centre
  measures "d429" vertical distance of origin A0.centre
  measures "d430" diameter of A0
extrude "Locating peg (1)" add sketch "Locating peg sketch (1)" against normal blind 0.8 bodies 5 in component "PRINT horizontal alignment key L"
ref_plane "WorkPlane1" through (0, 0, 5) normal (0, 0, 1) x (1, 0, 0) in component "PRINT horizontal alignment key R"
sketch "Key body sketch (2)" plane through (0, 0, 5) normal (0, 0, 1) x (1, 0, 0) in component "PRINT horizontal alignment key R"
  line L0 (188, 113) -> (192, 113)
  line L1 (192, 113) -> (192, 127)
  line L2 (192, 127) -> (188, 127)
  line L3 (188, 127) -> (188, 113)
  dimension "d435" = 188
  dimension "d436" = 113
  dimension "d437" = 4
  dimension "d438" = 14
  constraint horizontal L0
  constraint vertical L1
  constraint horizontal L2
  constraint vertical L3
  measures "d435" horizontal distance of origin L0.start
  measures "d436" vertical distance of origin L0.start
  measures "d437" horizontal distance of L0.start L0.end
  measures "d438" vertical distance of L0.end L1.end
extrude "Key body'" add sketch "Key body sketch (2)" along normal blind 2 separate body makes body 6 in component "PRINT horizontal alignment key R"
ref_plane "WorkPlane2" through (0, 0, 5) normal (0, 0, 1) x (1, 0, 0) in component "PRINT horizontal alignment key R"
sketch "Locating peg sketch (2)" plane through (0, 0, 5) normal (0, 0, 1) x (1, 0, 0) in component "PRINT horizontal alignment key R"
  circle A0 centre (190, 115) radius 1.5
  dimension "d443" = 190
  dimension "d444" = 115
  dimension "d445" = 3
  measures "d443" horizontal distance of origin A0.centre
  measures "d444" vertical distance of origin A0.centre
  measures "d445" diameter of A0
extrude "Locating peg'" add sketch "Locating peg sketch (2)" against normal blind 0.8 bodies 6 in component "PRINT horizontal alignment key R"
ref_plane "WorkPlane3" through (0, 0, 5) normal (0, 0, 1) x (1, 0, 0) in component "PRINT horizontal alignment key R"
sketch "Locating peg sketch (1) (2)" plane through (0, 0, 5) normal (0, 0, 1) x (1, 0, 0) in component "PRINT horizontal alignment key R"
  circle A0 centre (190, 125) radius 1.5
  dimension "d450" = 190
  dimension "d451" = 125
  dimension "d452" = 3
  measures "d450" horizontal distance of origin A0.centre
  measures "d451" vertical distance of origin A0.centre
  measures "d452" diameter of A0
extrude "Locating peg (1)'" add sketch "Locating peg sketch (1) (2)" against normal blind 0.8 bodies 6 in component "PRINT horizontal alignment key R"
ref_plane "WorkPlane1" through (0, 0, 5) normal (0, 0, 1) x (1, 0, 0) in component "PRINT vertical alignment key B"
sketch "Key spine sketch" plane through (0, 0, 5) normal (0, 0, 1) x (1, 0, 0) in component "PRINT vertical alignment key B"
  line L0 (118, 68) -> (122, 68)
  line L1 (122, 68) -> (122, 82)
  line L2 (122, 82) -> (118, 82)
  line L3 (118, 82) -> (118, 68)
  dimension "d457" = 118
  dimension "d458" = 68
  dimension "d459" = 4
  dimension "d460" = 14
  constraint horizontal L0
  constraint vertical L1
  constraint horizontal L2
  constraint vertical L3
  measures "d457" horizontal distance of origin L0.start
  measures "d458" vertical distance of origin L0.start
  measures "d459" horizontal distance of L0.start L0.end
  measures "d460" vertical distance of L0.end L1.end
extrude "Key spine" add sketch "Key spine sketch" along normal blind 2 separate body makes body 7 in component "PRINT vertical alignment key B"
ref_plane "WorkPlane2" through (0, 0, 5) normal (0, 0, 1) x (1, 0, 0) in component "PRINT vertical alignment key B"